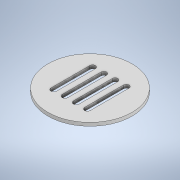
# Autodesk Inventor part: 4_4_capac_nr_4_6_mm
Saved by Autodesk Inventor 2022.6 (Build 266554000, 554)
## iProperties
Created: 2025-09-01
Part Number: 4_4_capac_nr_4_6_mm
Material: Generic
Document SubType Name: Modeling
Designer: Dragos Macovei
Density: 1 g/cm^3
Appearance: Default
Author: Dragos Macovei
Autodesk Inventor part; units mm, degrees
ref_plane "YZ Plane" through (0, 0, 0) normal (1, 0, 0) x (0, 1, 0)
ref_plane "XZ Plane" through (0, 0, 0) normal (0, 1, 0) x (-1, 0, 0)
ref_plane "XY Plane" through (0, 0, 0) normal (0, 0, 1) x (1, 0, 0)
sketch "Sketch1" plane through (0, 0, 0) normal (0, 1, 0) x (-1, 0, 0)
  circle A0 centre (0, 0) radius 75
  dimension "d0" = 150
  constraints: 1 centre point, 1 coincident
  measures "d0" diameter of A0
extrude "Extrusion1" add sketch "Sketch1" along normal blind 6
sketch "Sketch2" plane through (0, 6, 0) normal (0, 1, 0) x (1, 0, 0)
  circle A0 centre (0, 0) radius 75 projected
  circle A1 centre (0, 0) radius 60 construction
  circle A2 centre (30, 34.7214) radius 5
  circle A3 centre (30, -34.7214) radius 5
  line L0 (35, -34.7214) -> (35, 34.7214)
  line L1 (25, 34.7214) -> (25, -34.7214)
  line L2 (-40, 44.7214) -> (40, 44.7214)
  line L3 (40, 44.7214) -> (40, -44.7214)
  line L4 (40, -44.7214) -> (-40, -44.7214)
  line L5 (-40, -44.7214) -> (-40, 44.7214)
  circle A4 centre (-30, 34.7214) radius 5
  circle A5 centre (-30, -34.7214) radius 5
  line L6 (-25, -34.7214) -> (-25, 34.7214)
  line L7 (-35, 34.7214) -> (-35, -34.7214)
  circle A6 centre (-10, -34.7214) radius 5
  line L8 (-5, -34.7214) -> (-5, 34.7214)
  line L9 (-15, 34.7214) -> (-15, -34.7214)
  circle A7 centre (-10, 34.7214) radius 5
  circle A8 centre (10, 34.7214) radius 5
  line L10 (15, -34.7214) -> (15, 34.7214)
  line L11 (5, 34.7214) -> (5, -34.7214)
  circle A9 centre (10, -34.7214) radius 5
  dimension "d3" = 120
  dimension "d4" = 10
  dimension "d5" = 10
  dimension "d6" = 10
  dimension "d7" = 10
  dimension "d8" = 10
  dimension "d9" = 10
  dimension "d10" = 10
  dimension "d11" = 10
  dimension "d12" = 10
  dimension "d13" = 10
  dimension "d14" = 10
  dimension "d15" = 10
  dimension "d16" = 10
  dimension "d17" = 10
  dimension "d18" = 20
  dimension "d19" = 20
  dimension "d20" = 10
  dimension "d21" = 10
  dimension "d22" = 10
  dimension "d23" = 10
  dimension "d24" = 20
  dimension "d25" = 20
  dimension "d26" = 10
  dimension "d27" = 10
  dimension "d28" = 20
  constraints: 24 end point, 19 point on circle, 16 tangent, 9 centre point, 2 parallel, 1 coincident, 1 horizontal, 1 perpendicular
  measures "d3" diameter of A1
  measures "d4" diameter of A2
  measures "d5" diameter of A3
  measures "d6" distance from line of L3 A2.centre
  measures "d7" distance from line of A2.centre L2
  measures "d8" distance from line of L3 A3.centre
  measures "d9" distance from line of L4 A3.centre
  measures "d10" diameter of A4
  measures "d11" diameter of A5
  measures "d12" distance from line of L5 A4.centre
  measures "d13" distance from line of L5 A5.centre
  measures "d14" distance from line of L4 A5.centre
  measures "d15" distance from line of L2 A4.centre
  measures "d16" diameter of A7
  measures "d17" diameter of A6
  measures "d18" distance of A4.centre A7.centre
  measures "d19" distance of A5.centre A6.centre
  measures "d20" distance from line of A7.centre L2
  measures "d21" distance from line of A6.centre L4
  measures "d22" diameter of A8
  measures "d23" diameter of A9
  measures "d24" distance of A6.centre A9.centre
  measures "d25" distance of A7.centre A8.centre
  measures "d26" distance from line of A8.centre L2
  measures "d27" distance from line of L4 A9.centre
  measures "d28" distance of A3.centre A9.centre
extrude "Extrusion2" cut sketch "Sketch2" against normal through all contours A2 | L0 A3 L1 A2 | A3 | A4 | L6 A5 L7 A4 | A5 | A6 | A6 L9 A7 L8 | A7 | A8 | L10 A9 L11 A8 | A9
body "Solid1"
